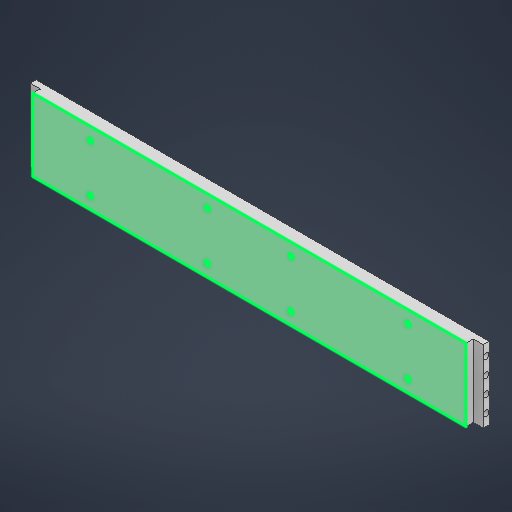
# Autodesk Inventor part: s1101mfd1014
Saved by Autodesk Inventor 2026.4 (Build 304435000, 435)
## iProperties
Created: 2026-11-02
Part Number: s1101mfd1014
Material: Genérico
Document SubType Name: Modeling
Designer: User
Density: 1 g/cm^3
Appearance: Padrão
Author: User
Autodesk Inventor part; units mm, degrees
sketch "Esboço1" plane through (0, 0, 0) normal (0, 0, 1) x (1, 0, 0)
  line L0 (0, -34.925) -> (437.9214, -34.925)
  line L1 (437.9214, -34.925) -> (437.9214, 34.925)
  line L2 (437.9214, 34.925) -> (0, 34.925)
  line L3 (0, 34.925) -> (0, -34.925)
  constraints: 8 end point, 2 parallel, 1 horizontal, 1 perpendicular
extrude "Extrusão1" add sketch "Esboço1" along normal blind 5.715
ref_plane "Plano de trabalho1" through (0, 0, 5.715) normal (0, 0, 1) x (1, 0, 0)
sketch "Esboço2" plane through (0, 0, 5.715) normal (0, 0, 1) x (1, 0, 0)
  line L0 (9.5377, -34.925) -> (428.3837, -34.925)
  line L1 (428.3837, -34.925) -> (428.3837, 34.925)
  line L2 (428.3837, 34.925) -> (9.5377, 34.925)
  line L3 (9.5377, 34.925) -> (9.5377, -34.925)
  constraints: 8 end point, 2 parallel, 1 horizontal, 1 perpendicular
extrude "Extrusão2" add sketch "Esboço2" along normal blind 6.985
ref_plane "Plano de trabalho2" through (0, 0, 0) normal (1, 0, 0) x (0, 1, 0)
sketch "Esboço3" plane through (0, 0, 0) normal (1, 0, 0) x (0, 1, 0)
  circle A0 centre (-24.003, 2.8575) radius 2.7432
  circle A1 centre (-8.001, 2.8575) radius 2.7432
  circle A2 centre (8.001, 2.8575) radius 2.7432
  circle A3 centre (24.003, 2.8575) radius 2.7432
  constraints: 4 centre point
extrude "Extrusão3" cut sketch "Esboço3" along normal blind 10.922
ref_plane "Plano de trabalho3" through (437.9214, 0, 0) normal (1, 0, 0) x (0, 1, 0)
sketch "Esboço4" plane through (437.9214, 0, 0) normal (1, 0, 0) x (0, 1, 0)
  circle A0 centre (-24.003, 2.8575) radius 2.7432
  circle A1 centre (-8.001, 2.8575) radius 2.7432
  circle A2 centre (8.001, 2.8575) radius 2.7432
  circle A3 centre (24.003, 2.8575) radius 2.7432
  constraints: 4 centre point
extrude "Extrusão4" cut sketch "Esboço4" against normal blind 10.922
ref_plane "Plano de trabalho4" through (0, 0, 12.7) normal (0, 0, 1) x (1, 0, 0)
sketch "Esboço5" plane through (0, 0, 12.7) normal (0, 0, 1) x (1, 0, 0)
  circle A0 centre (65.4431, -23.0124) radius 2.1082
  circle A1 centre (65.4431, 23.0124) radius 2.1082
  circle A2 centre (178.5493, -23.0124) radius 2.1082
  circle A3 centre (178.5493, 23.0124) radius 2.1082
  circle A4 centre (259.3721, -23.0124) radius 2.1082
  circle A5 centre (259.3721, 23.0124) radius 2.1082
  circle A6 centre (372.4783, -23.0124) radius 2.1082
  circle A7 centre (372.4783, 23.0124) radius 2.1082
  constraints: 8 centre point
extrude "Extrusão5" cut sketch "Esboço5" against normal through all
